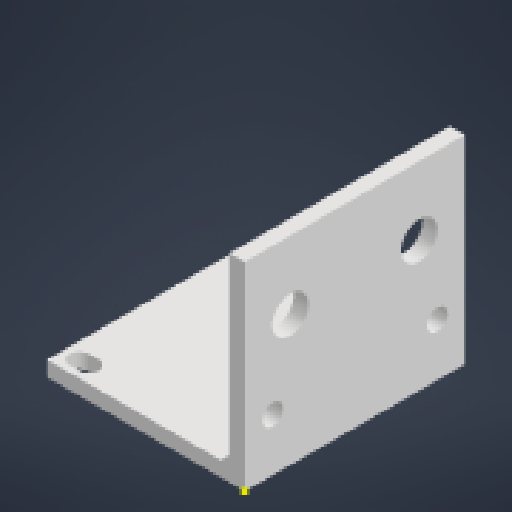
# Autodesk Inventor part: Sensor_Befestigung
Saved by Autodesk Inventor 2027.1 (Build 311270010, 270A)
## iProperties
Created: 2026-10-21
Part Number: Sensor_Befestigung
Material: Generic
Document SubType Name: Modeling
Designer: nicol
Density: 1 g/cm^3
Appearance: Default
Author: nicol
Autodesk Inventor part; units mm, degrees
ref_plane "YZ Plane" through (0, 0, 0) normal (1, 0, 0) x (0, 1, 0)
ref_plane "XZ Plane" through (0, 0, 0) normal (0, 1, 0) x (-1, 0, 0)
ref_plane "XY Plane" through (0, 0, 0) normal (0, 0, 1) x (1, 0, 0)
sketch "Sketch1" plane through (0, 0, 0) normal (1, 0, 0) x (0, 1, 0)
  line L0 (0, 0) -> (43.5, 0)
  line L1 (43.5, 0) -> (43.5, -48.2)
  line L2 (43.5, -48.2) -> (0, -48.2)
  line L3 (0, -48.2) -> (0, 0)
  point P0 (0, 0)
  dimension "d0" = 0
  dimension "d1" = 0
  dimension "d2" = 48.2
  dimension "d3" = 43.5
  constraints: 8 end point, 2 parallel, 1 horizontal, 1 perpendicular
  measures "d0" distance from line of point (0, 0) L0
  measures "d1" distance from line of point (0, 0) L3
  measures "d2" distance between parallel lines of L0 L2
  measures "d3" distance between parallel lines of L3 L1
extrude "Extrusion1" add sketch "Sketch1" along normal blind 3.3
sketch "Sketch2" plane through (0, 0, 0) normal (-1, 0, 0) x (0, 0, 1)
  line L0 (-48.2, 0) -> (0, 0)
  line L1 (0, 0) -> (0, 3.3)
  line L2 (0, 3.3) -> (-48.2, 3.3)
  line L3 (-48.2, 3.3) -> (-48.2, 0)
  line L4 (-48.2, 0) -> (-48.2, 43.5) projected
  line L5 (0, 0) -> (-48.2, 0) projected
  line L6 (0, 43.5) -> (0, 0) projected
  dimension "d6" = 0
  dimension "d7" = 0
  dimension "d8" = 0
  dimension "d9" = 3.3
  constraints: 8 end point, 2 parallel, 1 horizontal, 1 perpendicular
  measures "d6" distance between parallel lines of L4 L3
  measures "d7" distance between parallel lines of L5 L0
  measures "d8" distance between parallel lines of L6 L1
  measures "d9" distance between parallel lines of L0 L2
extrude "Extrusion2" add sketch "Sketch2" along normal blind 40
sketch "Sketch3" plane through (3.3, 0, -48.2) normal (0, -1, 0) x (1, 0, 0)
  line L0 (-8.7, 5.7) -> (-10.8, 5.7)
  line L1 (-10.8, 1.5) -> (-8.7, 1.5)
  line L2 (-37.7, 46.7) -> (-39.8, 46.7)
  line L3 (-39.8, 42.5) -> (-37.7, 42.5)
  arc A0 (-8.7, 1.5) -> (-8.7, 5.7) centre (-8.7, 3.6) ccw
  arc A1 (-10.8, 5.7) -> (-10.8, 1.5) centre (-10.8, 3.6) ccw
  arc A2 (-37.7, 42.5) -> (-37.7, 46.7) centre (-37.7, 44.6) ccw
  arc A3 (-39.8, 46.7) -> (-39.8, 42.5) centre (-39.8, 44.6) ccw
  line L4 (0, 0) -> (-43.3, 0) projected
  line L5 (0, 48.2) -> (0, 0) projected
  line L6 (-43.3, 48.2) -> (0, 48.2) projected
  line L7 (-43.3, 0) -> (-43.3, 48.2) projected
  point P0 (-3.3, 48.2)
  dimension "d12" = 1.5
  dimension "d13" = 4.2
  dimension "d14" = 2.1
  dimension "d15" = 8.7
  dimension "d16" = 1.5
  dimension "d17" = 4.2
  dimension "d20" = 2.1
  dimension "d21" = 3.5
  constraints: 8 end point, 8 point on circle, 8 tangent, 4 centre point, 2 horizontal, 2 parallel
  measures "d12" distance between parallel lines of L4 L1
  measures "d13" distance between parallel lines of L0 L1
  measures "d14" distance of A0.centre A1.centre
  measures "d15" distance from line of L5 A0.centre
  measures "d16" distance between parallel lines of L6 L2
  measures "d17" distance between parallel lines of L3 L2
  measures "d20" distance of A3.centre A2.centre
  measures "d21" distance from line of L7 A3.centre
extrude "Extrusion3" cut sketch "Sketch3" against normal blind 3.3 contours A0 L1 A1 L0 | A2 L3 A3 L2
chamfer "Chamfer1" distance 2 angle 45 1 edges at (0, 3.3, -24.1)
sketch "Sketch4" plane through (3.3, 0, 0) normal (1, 0, 0) x (0, 0, -1)
  point P0 (0, 0)
sketch "Sketch5" plane through (3.3, 0, 0) normal (1, 0, 0) x (0, 0, -1)
  circle A0 centre (38.2, 28.5) radius 4
  circle A1 centre (10, 28.5) radius 4
  line L0 (48.2, 43.5) -> (0, 43.5) projected
  line L1 (48.2, 0) -> (48.2, 43.5) projected
  line L2 (0, 43.5) -> (0, 0) projected
  dimension "d27" = 15
  dimension "d28" = 15
  dimension "d29" = 8
  dimension "d30" = 8
  dimension "d31" = 10
  dimension "d32" = 10
  constraints: 2 centre point
  measures "d27" distance from line of L0 A1.centre
  measures "d28" distance from line of L0 A0.centre
  measures "d29" diameter of A0
  measures "d30" diameter of A1
  measures "d31" distance from line of L1 A0.centre
  measures "d32" distance from line of L2 A1.centre
extrude "Extrusion4" cut sketch "Sketch5" against normal blind 3.3
sketch "Sketch6" plane through (3.3, 0, 0) normal (1, 0, 0) x (0, 0, -1)
  circle A0 centre (6.1, 11.5) radius 2.25
  circle A1 centre (42.1, 11.5) radius 2.25
  line L0 (0, 43.5) -> (0, 0) projected
  line L1 (48.2, 0) -> (48.2, 43.5) projected
  line L2 (0, 0) -> (48.2, 0) projected
  dimension "d35" = 36
  dimension "d36" = 0
  dimension "d37" = 48.2
  dimension "d38" = 6.1
  dimension "d39" = 11.5
  dimension "d40" = 4.5
  dimension "d41" = 4.5
  constraints: 2 centre point
  measures "d35" distance of A1.centre A0.centre
  measures "d36" vertical distance of A1.centre A0.centre
  measures "d37" distance between parallel lines of L0 L1
  measures "d38" distance from line of L0 A0.centre
  measures "d39" distance from line of L2 A1.centre
  measures "d40" diameter of A1
  measures "d41" diameter of A0
extrude "Extrusion5" cut sketch "Sketch6" against normal blind 3.3
body "Solid1"
